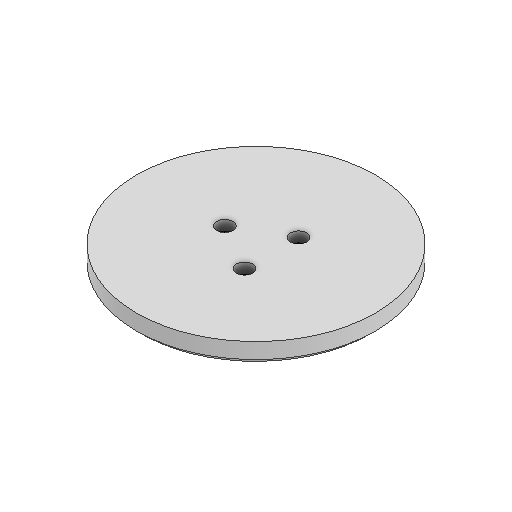
# Autodesk Inventor part: 3DP_PLA_B_Axis_End_Cap
Saved by Autodesk Inventor 2027 (Build 310192060, 192F)
## iProperties
Created: 2026-01-18
Part Number: 3DP_PLA_B_Axis_End_Cap
Material: Generic
Document SubType Name: Modeling
Designer: Andrzej
Density: 1 g/cm^3
Appearance: Default
Author: Andrzej
Autodesk Inventor part; units mm, degrees
ref_plane "YZ Plane" through (0, 0, 0) normal (1, 0, 0) x (0, 1, 0)
ref_plane "XZ Plane" through (0, 0, 0) normal (0, 1, 0) x (-1, 0, 0)
ref_plane "XY Plane" through (0, 0, 0) normal (0, 0, 1) x (1, 0, 0)
sketch "Sketch1" plane through (0, 0, 0) normal (0, 1, 0) x (-1, 0, 0)
  circle A0 centre (0, 0) radius 46
  point P0 (12, 0)
  point P1 (-6, 10.3923)
  point P2 (-6, -10.3923)
  dimension "d0" = 92
  dimension "d1" = 12
  dimension "d4" = 360
  constraints: 1 centre point, 1 coincident, 4 other
  measures "d0" diameter of A0
  measures "d1" distance of point (0, 0) point (12, 0)
extrude "Extrusion1" add sketch "Sketch1" along normal blind 8
hole "Hole1" at (-12, 0, 0) at (6, 0, 10.3923) at (6, 0, -10.3923) direction (0, 1, 0) diameter 6.2 end through all
chamfer "Chamfer1" distance 2 angle 45 1 edges at (46, 0, 0)
sketch "Sketch2" plane through (0, 0, 0) normal (0, -1, 0) x (1, 0, 0)
  point P0 (0, 0)
sketch "Sketch3" plane through (0, 0, 0) normal (0, -1, 0) x (1, 0, 0)
  circle A0 centre (-12, 0) radius 3.1 projected
  circle A1 centre (6, 10.3923) radius 3.1 projected
  circle A2 centre (6, -10.3923) radius 3.1 projected
  circle A3 centre (0, 0) radius 44 projected
  line L0 (11.25, 7.3612) -> (6, 4.3301)
  line L1 (6, 4.3301) -> (0.75, 7.3612)
  line L2 (0.75, 7.3612) -> (0.75, 13.4234)
  line L3 (0.75, 13.4234) -> (6, 16.4545)
  line L4 (6, 16.4545) -> (11.25, 13.4234)
  line L5 (11.25, 13.4234) -> (11.25, 7.3612)
  line L6 (11.25, -13.4234) -> (6, -16.4545)
  line L7 (6, -16.4545) -> (0.75, -13.4234)
  line L8 (0.75, -13.4234) -> (0.75, -7.3612)
  line L9 (0.75, -7.3612) -> (6, -4.3301)
  line L10 (6, -4.3301) -> (11.25, -7.3612)
  line L11 (11.25, -7.3612) -> (11.25, -13.4234)
  line L12 (-6.75, -3.0311) -> (-12, -6.0622)
  line L13 (-12, -6.0622) -> (-17.25, -3.0311)
  line L14 (-17.25, -3.0311) -> (-17.25, 3.0311)
  line L15 (-17.25, 3.0311) -> (-12, 6.0622)
  line L16 (-12, 6.0622) -> (-6.75, 3.0311)
  line L17 (-6.75, 3.0311) -> (-6.75, -3.0311)
  dimension "d18" = 10.5
  dimension "d19" = 10.5
  dimension "d20" = 10.5
  constraints: 36 end point, 3 coincident, 2 equal length, 39 other
  measures "d18" distance between parallel lines of L2 L5
  measures "d19" distance between parallel lines of L11 L8
  measures "d20" distance between parallel lines of L17 L14
extrude "Extrusion2" cut sketch "Sketch3" against normal blind 4 contours L0 L1 L2 L3 L4 L5 | L6 L7 L8 L9 L10 L11 | L12 L13 L14 L15 L16 L17
sketch "Sketch4" plane through (0, 0, 0) normal (0, -1, 0) x (1, 0, 0)
  line L0 (14.1699, -34.5429) -> (22.8301, -29.5429)
  line L1 (22.8301, -29.5429) -> (21, -36.3731)
  line L2 (14.1699, -34.5429) -> (21, -36.3731)
  line L3 (-5, -37) -> (8.9247, -37) construction
  point P0 (0, 0)
  point P1 (17.6283, -30.4768)
  dimension "d23" = 10
  dimension "d25" = 45
  dimension "d27" = 15
  dimension "d28" = 37
  dimension "d29" = -14.1699
  constraints: 8 end point, 1 horizontal
  measures "d23" distance of L0.start L0.end
  measures "d25" angle of L0 L1
  measures "d27" angle of L2 L3
  measures "d28" distance from line of point (0, 0) L0
  measures "d29" horizontal distance of point (0, 0) L0.start
extrude "Extrusion3" cut sketch "Sketch4" against normal blind 1
equation "\"d19\" = d18"
equation "\"d20\" = d18"
body "Solid1"
